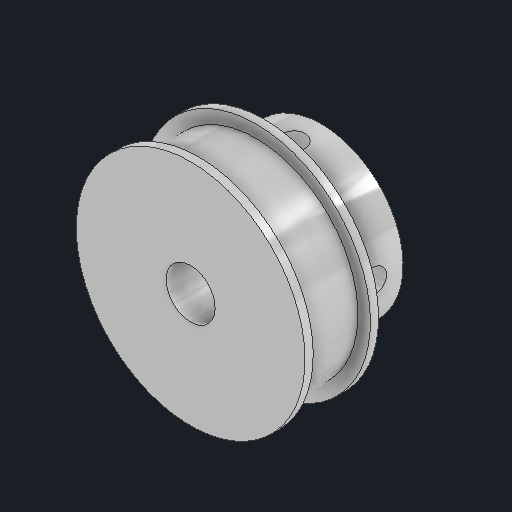
# Autodesk Inventor part: gt2_40T_bore6
Saved by Autodesk Inventor 2027.1 (Build 311270010, 270A)
## iProperties
Created: 2026-11-04
Part Number: gt2_40T_bore6
Material: Generic
Description: GT2 40T pulley, 6 mm belt, 6 mm bore, hub 20 x 7 with 2x M3 grub
Document SubType Name: Modeling
Designer: Claude (from photos)
Density: 1 g/cm^3
Appearance: Aluminum - Polished
Author: alexg
Autodesk Inventor part; units mm, degrees
ref_plane "YZ Plane" through (0, 0, 0) normal (1, 0, 0) x (0, 1, 0)
ref_plane "XZ Plane" through (0, 0, 0) normal (0, 1, 0) x (-1, 0, 0)
ref_plane "XY Plane" through (0, 0, 0) normal (0, 0, 1) x (1, 0, 0)
sketch "Pulley body sketch" plane through (0, 0, 0) normal (1, 0, 0) x (0, 1, 0)
  line L0 (3, 0) -> (3, 16)
  line L1 (3, 16) -> (14, 16)
  line L2 (14, 16) -> (14, 15)
  line L3 (14, 15) -> (12.475, 15)
  line L4 (12.475, 15) -> (12.475, 8)
  line L5 (12.475, 8) -> (14, 8)
  line L6 (14, 8) -> (14, 7)
  line L7 (14, 7) -> (10, 7)
  line L8 (10, 7) -> (10, 0)
  line L9 (10, 0) -> (3, 0)
  line L10 (0, -3.2) -> (0, 19.2) projected
  constraints: 20 end point
revolve "Pulley body" add sketch "Pulley body sketch" angle 360 about axis through (0, 0, -10) along (0, 0, 1)
sketch "Grub M3 #1 sketch" plane through (0, 0, 0) normal (0, 1, 0) x (-1, 0, 0)
  circle A0 centre (0, 3.5) radius 1.5
  constraints: 1 centre point
extrude "Grub M3 #1" cut sketch "Grub M3 #1 sketch" along normal blind 12
sketch "Grub M3 #2 sketch" plane through (0, 0, 0) normal (1, 0, 0) x (0, 1, 0)
  circle A0 centre (0, 3.5) radius 1.5
  constraints: 1 centre point
extrude "Grub M3 #2" cut sketch "Grub M3 #2 sketch" along normal blind 12
body "Solid1"
